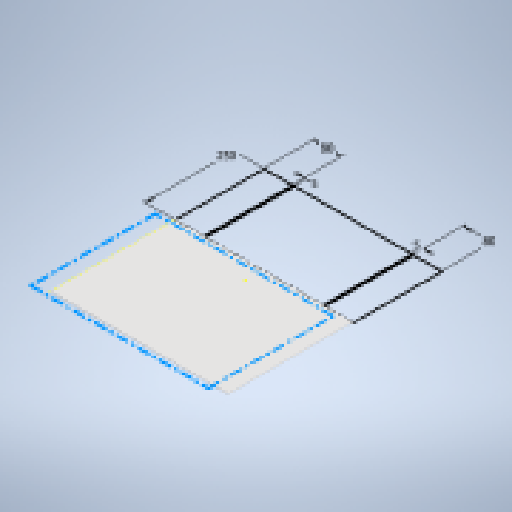
# Autodesk Inventor part: полигон
Saved by Autodesk Inventor 2024.2 (Build 282272000, 272)
## iProperties
Created: 2026-10-08
Part Number: полигон
Material: Типовые
Document SubType Name: Modeling
Designer: User
Density: 1 g/cm^3
Appearance: По умолчанию
Author: User
Autodesk Inventor part; units mm, degrees
ref_plane "YZ Plane" through (0, 0, 0) normal (1, 0, 0) x (0, 1, 0)
ref_plane "XZ Plane" through (0, 0, 0) normal (0, 1, 0) x (-1, 0, 0)
ref_plane "XY Plane" through (0, 0, 0) normal (0, 0, 1) x (1, 0, 0)
sketch "Эскиз1" plane through (0, 0, 0) normal (0, 1, 0) x (-1, 0, 0)
  line L0 (-250, -300) -> (250, -300)
  line L1 (250, -300) -> (250, 300)
  line L2 (250, 300) -> (-250, 300)
  line L3 (-250, 300) -> (-250, -300)
  line L4 (-250, -300) -> (250, 300) construction
  line L5 (250, -300) -> (-250, 300) construction
  line L6 (250, -50) -> (-250, -50)
  point P0 (0, 0)
  dimension "d0" = 500
  dimension "d1" = 600
  dimension "d2" = 350
  constraints: 14 end point, 2 midpoint, 2 parallel, 2 perpendicular, 2 point on line, 1 horizontal
  measures "d0" distance of L1.end L2.end
  measures "d1" distance of L2.end L0.start
  measures "d2" distance between parallel lines of L2 L6
extrude "Выдавливание1" add sketch "Эскиз1" along normal blind 2 contours L3 L2 L1 L6
sketch "Эскиз2" plane through (0, 0, 0) normal (0, -1, 0) x (1, 0, 0)
  line L0 (-250, -50) -> (-250, 300) projected
  line L1 (-250, -50) -> (250, -50)
  line L2 (250, -50) -> (250, -300)
  line L3 (250, -300) -> (-250, -300)
  line L4 (-250, -300) -> (-250, -50)
  line L5 (-170, -50) -> (-170, -300)
  line L6 (250, -50) -> (-250, -50) projected
  line L7 (170, -50) -> (170, -300)
  line L8 (-165, -50) -> (-165, -300)
  line L9 (165, -50) -> (165, -300)
  point P0 (0, 0)
  dimension "d5" = 250
  dimension "d6" = 80
  dimension "d7" = 80
  dimension "d8" = 5
  dimension "d9" = 5
  constraints: 16 end point, 8 point on line, 5 perpendicular, 2 parallel, 1 horizontal
  measures "d5" distance between parallel lines of L3 L1
  measures "d6" distance between parallel lines of L4 L5
  measures "d7" distance between parallel lines of L2 L7
  measures "d8" distance between parallel lines of L5 L8
  measures "d9" distance between parallel lines of L7 L9
